Autodesk Fusion 360 part; units mm, degrees
(part 3 of 3)
sketch "V3 label POWER  /  LOCK  /  PURGE" plane through (0, 0, 67) normal (0, 0, 1) x (1, 0, 0) in component "02 LID - LCD buttons LEDs"
  line L0 (10, 78) -> (130, 78) construction
  line L1 (130, 78) -> (130, 86) construction
  line L2 (130, 86) -> (10, 86) construction
  line L3 (10, 86) -> (10, 78) construction
  dimension "d880" = 4
  text T0 "POWER  /  LOCK  /  PURGE" font "Arial" height 4 align centre middle in box 120 x 8 at (10, 78) x (1, 0) y (0, 1) spacing 1 kerned
extrude "V3 engraving POWER  /  LOCK  /  PURGE" cut sketch "V3 label POWER  /  LOCK  /  PURGE" against normal blind 0.6 text T0 bodies 2 in component "02 LID - LCD buttons LEDs"
ref_plane "WorkPlane44" through (0, 0, 67) normal (0, 0, 1) x (1, 0, 0) in component "02 LID - LCD buttons LEDs"
sketch "V3 label CONTROL UNIT" plane through (0, 0, 67) normal (0, 0, 1) x (1, 0, 0) in component "02 LID - LCD buttons LEDs"
  line L0 (20, 11) -> (120, 11) construction
  line L1 (120, 11) -> (120, 19) construction
  line L2 (120, 19) -> (20, 19) construction
  line L3 (20, 19) -> (20, 11) construction
  dimension "d886" = 4
  text T0 "CONTROL UNIT" font "Arial" height 4 align centre middle in box 100 x 8 at (20, 11) x (1, 0) y (0, 1) spacing 1 kerned
extrude "V3 engraving CONTROL UNIT" cut sketch "V3 label CONTROL UNIT" against normal blind 0.6 text T0 bodies 2 in component "02 LID - LCD buttons LEDs"
ref_plane "WorkPlane12" through (0, 0, 68.9) normal (0, 0, 1) x (1, 0, 0) in component "V2 removable control fascia"
sketch "V3 tactile number bars sketch" plane through (0, 0, 68.9) normal (0, 0, 1) x (1, 0, 0) in component "V2 removable control fascia"
  line L0 (61.98, 60) -> (62.78, 60)
  line L1 (62.78, 60) -> (62.78, 63.2)
  line L2 (62.78, 63.2) -> (61.98, 63.2)
  line L3 (61.98, 63.2) -> (61.98, 60)
extrude "V3 tactile number bars" cut sketch "V3 tactile number bars sketch" along normal blind 0.8 bodies 7 in component "V2 removable control fascia"
ref_plane "WorkPlane13" through (0, 0, 68.9) normal (0, 0, 1) x (1, 0, 0) in component "V2 removable control fascia"
sketch "V3 tactile number bars sketch (1)" plane through (0, 0, 68.9) normal (0, 0, 1) x (1, 0, 0) in component "V2 removable control fascia"
  line L0 (68.8, 60) -> (69.6, 60)
  line L1 (69.6, 60) -> (69.6, 63.2)
  line L2 (69.6, 63.2) -> (68.8, 63.2)
  line L3 (68.8, 63.2) -> (68.8, 60)
extrude "V3 tactile number bars (1)" cut sketch "V3 tactile number bars sketch (1)" along normal blind 0.8 bodies 7 in component "V2 removable control fascia"
ref_plane "WorkPlane14" through (0, 0, 68.9) normal (0, 0, 1) x (1, 0, 0) in component "V2 removable control fascia"
sketch "V3 tactile number bars sketch (2)" plane through (0, 0, 68.9) normal (0, 0, 1) x (1, 0, 0) in component "V2 removable control fascia"
  line L0 (70.4, 60) -> (71.2, 60)
  line L1 (71.2, 60) -> (71.2, 63.2)
  line L2 (71.2, 63.2) -> (70.4, 63.2)
  line L3 (70.4, 63.2) -> (70.4, 60)
extrude "V3 tactile number bars (2)" cut sketch "V3 tactile number bars sketch (2)" along normal blind 0.8 bodies 7 in component "V2 removable control fascia"
ref_plane "WorkPlane15" through (0, 0, 68.9) normal (0, 0, 1) x (1, 0, 0) in component "V2 removable control fascia"
sketch "V3 tactile number bars sketch (3)" plane through (0, 0, 68.9) normal (0, 0, 1) x (1, 0, 0) in component "V2 removable control fascia"
  line L0 (75.62, 60) -> (76.42, 60)
  line L1 (76.42, 60) -> (76.42, 63.2)
  line L2 (76.42, 63.2) -> (75.62, 63.2)
  line L3 (75.62, 63.2) -> (75.62, 60)
extrude "V3 tactile number bars (3)" cut sketch "V3 tactile number bars sketch (3)" along normal blind 0.8 bodies 7 in component "V2 removable control fascia"
ref_plane "WorkPlane16" through (0, 0, 68.9) normal (0, 0, 1) x (1, 0, 0) in component "V2 removable control fascia"
sketch "V3 tactile number bars sketch (4)" plane through (0, 0, 68.9) normal (0, 0, 1) x (1, 0, 0) in component "V2 removable control fascia"
  line L0 (77.22, 60) -> (78.02, 60)
  line L1 (78.02, 60) -> (78.02, 63.2)
  line L2 (78.02, 63.2) -> (77.22, 63.2)
  line L3 (77.22, 63.2) -> (77.22, 60)
extrude "V3 tactile number bars (4)" cut sketch "V3 tactile number bars sketch (4)" along normal blind 0.8 bodies 7 in component "V2 removable control fascia"
ref_plane "WorkPlane17" through (0, 0, 68.9) normal (0, 0, 1) x (1, 0, 0) in component "V2 removable control fascia"
sketch "V3 tactile number bars sketch (5)" plane through (0, 0, 68.9) normal (0, 0, 1) x (1, 0, 0) in component "V2 removable control fascia"
  line L0 (78.82, 60) -> (79.62, 60)
  line L1 (79.62, 60) -> (79.62, 63.2)
  line L2 (79.62, 63.2) -> (78.82, 63.2)
  line L3 (78.82, 63.2) -> (78.82, 60)
extrude "V3 tactile number bars (5)" cut sketch "V3 tactile number bars sketch (5)" along normal blind 0.8 bodies 7 in component "V2 removable control fascia"
ref_plane "WorkPlane1" through (0, 0, 8) normal (0, 0, 1) x (1, 0, 0) in component "REF relay envelope 75.5x55x20 - variant not confirmed"
sketch "Relay PCB envelope sketch" plane through (0, 0, 8) normal (0, 0, 1) x (1, 0, 0) in component "REF relay envelope 75.5x55x20 - variant not confirmed"
  line L0 (32.25, 112) -> (107.75, 112)
  line L1 (107.75, 112) -> (107.75, 167)
  line L2 (107.75, 167) -> (32.25, 167)
  line L3 (32.25, 167) -> (32.25, 112)
extrude "Relay PCB envelope" add sketch "Relay PCB envelope sketch" along normal blind 1.6 separate body makes body 33 in component "REF relay envelope 75.5x55x20 - variant not confirmed"
ref_plane "WorkPlane2" through (0, 0, 9.6) normal (0, 0, 1) x (1, 0, 0) in component "REF relay envelope 75.5x55x20 - variant not confirmed"
sketch "SRD relay envelope 1 sketch" plane through (0, 0, 9.6) normal (0, 0, 1) x (1, 0, 0) in component "REF relay envelope 75.5x55x20 - variant not confirmed"
  line L0 (36.75, 131) -> (52.25, 131)
  line L1 (52.25, 131) -> (52.25, 150)
  line L2 (52.25, 150) -> (36.75, 150)
  line L3 (36.75, 150) -> (36.75, 131)
extrude "SRD relay envelope 1" add sketch "SRD relay envelope 1 sketch" along normal blind 15.5 separate body makes body 34 in component "REF relay envelope 75.5x55x20 - variant not confirmed"
ref_plane "WorkPlane3" through (0, 0, 9.6) normal (0, 0, 1) x (1, 0, 0) in component "REF relay envelope 75.5x55x20 - variant not confirmed"
sketch "SRD relay envelope 2 sketch" plane through (0, 0, 9.6) normal (0, 0, 1) x (1, 0, 0) in component "REF relay envelope 75.5x55x20 - variant not confirmed"
  line L0 (54.05, 131) -> (69.55, 131)
  line L1 (69.55, 131) -> (69.55, 150)
  line L2 (69.55, 150) -> (54.05, 150)
  line L3 (54.05, 150) -> (54.05, 131)
extrude "SRD relay envelope 2" add sketch "SRD relay envelope 2 sketch" along normal blind 15.5 separate body makes body 35 in component "REF relay envelope 75.5x55x20 - variant not confirmed"
ref_plane "WorkPlane4" through (0, 0, 9.6) normal (0, 0, 1) x (1, 0, 0) in component "REF relay envelope 75.5x55x20 - variant not confirmed"
sketch "SRD relay envelope 3 sketch" plane through (0, 0, 9.6) normal (0, 0, 1) x (1, 0, 0) in component "REF relay envelope 75.5x55x20 - variant not confirmed"
  line L0 (71.35, 131) -> (86.85, 131)
  line L1 (86.85, 131) -> (86.85, 150)
  line L2 (86.85, 150) -> (71.35, 150)
  line L3 (71.35, 150) -> (71.35, 131)
extrude "SRD relay envelope 3" add sketch "SRD relay envelope 3 sketch" along normal blind 15.5 separate body makes body 36 in component "REF relay envelope 75.5x55x20 - variant not confirmed"
ref_plane "WorkPlane5" through (0, 0, 9.6) normal (0, 0, 1) x (1, 0, 0) in component "REF relay envelope 75.5x55x20 - variant not confirmed"
sketch "SRD relay envelope 4 sketch" plane through (0, 0, 9.6) normal (0, 0, 1) x (1, 0, 0) in component "REF relay envelope 75.5x55x20 - variant not confirmed"
  line L0 (88.65, 131) -> (104.15, 131)
  line L1 (104.15, 131) -> (104.15, 150)
  line L2 (104.15, 150) -> (88.65, 150)
  line L3 (88.65, 150) -> (88.65, 131)
extrude "SRD relay envelope 4" add sketch "SRD relay envelope 4 sketch" along normal blind 15.5 separate body makes body 37 in component "REF relay envelope 75.5x55x20 - variant not confirmed"
ref_plane "WorkPlane6" through (0, 0, 9.6) normal (0, 0, 1) x (1, 0, 0) in component "REF relay envelope 75.5x55x20 - variant not confirmed"
sketch "Terminal strip envelope sketch" plane through (0, 0, 9.6) normal (0, 0, 1) x (1, 0, 0) in component "REF relay envelope 75.5x55x20 - variant not confirmed"
  line L0 (37, 155) -> (103, 155)
  line L1 (103, 155) -> (103, 165)
  line L2 (103, 165) -> (37, 165)
  line L3 (37, 165) -> (37, 155)
extrude "Terminal strip envelope" add sketch "Terminal strip envelope sketch" along normal blind 12 separate body makes body 38 in component "REF relay envelope 75.5x55x20 - variant not confirmed"
ref_plane "WorkPlane7" through (0, 0, 9.6) normal (0, 0, 1) x (1, 0, 0) in component "REF relay envelope 75.5x55x20 - variant not confirmed"
sketch "Control connector reserve sketch" plane through (0, 0, 9.6) normal (0, 0, 1) x (1, 0, 0) in component "REF relay envelope 75.5x55x20 - variant not confirmed"
  line L0 (41, 114) -> (77, 114)
  line L1 (77, 114) -> (77, 119)
  line L2 (77, 119) -> (41, 119)
  line L3 (41, 119) -> (41, 114)
extrude "Control connector reserve" add sketch "Control connector reserve sketch" along normal blind 18.4 separate body makes body 39 in component "REF relay envelope 75.5x55x20 - variant not confirmed"
ref_plane "WorkPlane1" through (0, 0, 49.6) normal (0, 0, 1) x (1, 0, 0) in component "REF LCD2004 98x60 - 93x55 mounting - conservative thickness"
sketch "LCD PCB 98x60 sketch" plane through (0, 0, 49.6) normal (0, 0, 1) x (1, 0, 0) in component "REF LCD2004 98x60 - 93x55 mounting - conservative thickness"
  line L0 (21, 98) -> (119, 98)
  line L1 (119, 98) -> (119, 158)
  line L2 (119, 158) -> (21, 158)
  line L3 (21, 158) -> (21, 98)
extrude "LCD PCB 98x60" add sketch "LCD PCB 98x60 sketch" along normal blind 1.6 separate body makes body 40 in component "REF LCD2004 98x60 - 93x55 mounting - conservative thickness"
ref_plane "WorkPlane2" through (0, 0, 49.5) normal (0, 0, 1) x (1, 0, 0) in component "REF LCD2004 98x60 - 93x55 mounting - conservative thickness"
sketch "LCD minimum published hole diameter sketch" plane through (0, 0, 49.5) normal (0, 0, 1) x (1, 0, 0) in component "REF LCD2004 98x60 - 93x55 mounting - conservative thickness"
  circle A0 centre (23.5, 100.5) radius 1.25
  circle A1 centre (116.5, 100.5) radius 1.25
  circle A2 centre (23.5, 155.5) radius 1.25
  circle A3 centre (116.5, 155.5) radius 1.25
extrude "LCD minimum published hole diameter" cut sketch "LCD minimum published hole diameter sketch" along normal blind 1.8 bodies 40 in component "REF LCD2004 98x60 - 93x55 mounting - conservative thickness"
ref_plane "WorkPlane3" through (0, 0, 51.2) normal (0, 0, 1) x (1, 0, 0) in component "REF LCD2004 98x60 - 93x55 mounting - conservative thickness"
sketch "LCD bezel depth envelope sketch" plane through (0, 0, 51.2) normal (0, 0, 1) x (1, 0, 0) in component "REF LCD2004 98x60 - 93x55 mounting - conservative thickness"
  line L0 (21.5, 108.8) -> (118.5, 108.8)
  line L1 (118.5, 108.8) -> (118.5, 147.2)
  line L2 (118.5, 147.2) -> (21.5, 147.2)
  line L3 (21.5, 147.2) -> (21.5, 108.8)
extrude "LCD bezel depth envelope" add sketch "LCD bezel depth envelope sketch" along normal blind 12 separate body makes body 41 in component "REF LCD2004 98x60 - 93x55 mounting - conservative thickness"
ref_plane "WorkPlane4" through (0, 0, 63.2) normal (0, 0, 1) x (1, 0, 0) in component "REF LCD2004 98x60 - 93x55 mounting - conservative thickness"
sketch "LCD viewing area envelope sketch" plane through (0, 0, 63.2) normal (0, 0, 1) x (1, 0, 0) in component "REF LCD2004 98x60 - 93x55 mounting - conservative thickness"
  line L0 (31.5, 115.4) -> (108.5, 115.4)
  line L1 (108.5, 115.4) -> (108.5, 140.6)
  line L2 (108.5, 140.6) -> (31.5, 140.6)
  line L3 (31.5, 140.6) -> (31.5, 115.4)
extrude "LCD viewing area envelope" add sketch "LCD viewing area envelope sketch" along normal blind 0.1 separate body makes body 42 in component "REF LCD2004 98x60 - 93x55 mounting - conservative thickness"
ref_plane "WorkPlane5" through (0, 0, 39.2) normal (0, 0, 1) x (1, 0, 0) in component "REF LCD2004 98x60 - 93x55 mounting - conservative thickness"
sketch "LCD I2C backpack reserve sketch" plane through (0, 0, 39.2) normal (0, 0, 1) x (1, 0, 0) in component "REF LCD2004 98x60 - 93x55 mounting - conservative thickness"
  line L0 (32, 100) -> (74, 100)
  line L1 (74, 100) -> (74, 118)
  line L2 (74, 118) -> (32, 118)
  line L3 (32, 118) -> (32, 100)
extrude "LCD I2C backpack reserve" add sketch "LCD I2C backpack reserve sketch" along normal blind 10.4 separate body makes body 43 in component "REF LCD2004 98x60 - 93x55 mounting - conservative thickness"
component "01 BASE - PCB at bottom" placed x (1, 0, 0) y (0, 1, 0) z (0, 0, 1) at (0, 0, 0)
component "02 LID - LCD buttons LEDs" placed x (1, 0, 0) y (0, 1, 0) z (0, 0, 1) at (0, 0, 0)
component "V2 MAIN clamp 1" placed x (1, 0, 0) y (0, 1, 0) z (0, 0, 1) at (0, 0, 0)
component "V2 MAIN clamp 2" placed x (1, 0, 0) y (0, 1, 0) z (0, 0, 1) at (0, 0, 0)
component "V2 MAIN clamp 3" placed x (1, 0, 0) y (0, 1, 0) z (0, 0, 1) at (0, 0, 0)
component "V2 MAIN clamp 4" placed x (1, 0, 0) y (0, 1, 0) z (0, 0, 1) at (0, 0, 0)
component "V2 removable control fascia" placed x (1, 0, 0) y (0, 1, 0) z (0, 0, 1) at (0, 0, 0)
component "V2 control PCB removable carrier" placed x (1, 0, 0) y (0, 1, 0) z (0, 0, 1) at (0, 0, 0)
component "V2 captured tactile plunger 1" placed x (1, 0, 0) y (0, 1, 0) z (0, 0, 1) at (0, 0, 0)
component "V2 captured tactile plunger 2" placed x (1, 0, 0) y (0, 1, 0) z (0, 0, 1) at (0, 0, 0)
component "V2 captured tactile plunger 3" placed x (1, 0, 0) y (0, 1, 0) z (0, 0, 1) at (0, 0, 0)
component "REF main board 90x80x20 - photo estimate" placed x (1, 0, 0) y (0, 1, 0) z (0, 0, 1) at (0, 0, 0)
component "REF actual combined buttons LEDs PCB - estimated" placed x (1, 0, 0) y (0, 1, 0) z (0, 0, 1) at (0, 0, 0)
component "V3 RELAY adjustable clamp 1" placed x (1, 0, 0) y (0, 1, 0) z (0, 0, 1) at (0, 0, 0)
component "V3 RELAY adjustable clamp 2" placed x (1, 0, 0) y (0, 1, 0) z (0, 0, 1) at (0, 0, 0)
component "V3 RELAY adjustable clamp 3" placed x (1, 0, 0) y (0, 1, 0) z (0, 0, 1) at (0, 0, 0)
component "V3 RELAY adjustable clamp 4" placed x (1, 0, 0) y (0, 1, 0) z (0, 0, 1) at (0, 0, 0)
component "REF relay envelope 75.5x55x20 - variant not confirmed" placed x (1, 0, 0) y (0, 1, 0) z (0, 0, 1) at (0, 0, 0)
component "REF LCD2004 98x60 - 93x55 mounting - conservative thickness" placed x (1, 0, 0) y (0, 1, 0) z (0, 0, 1) at (0, 0, 0)
equation "button_d = 12.2 mm" comment "ASSUMED: measure actual panel button"
equation "led_d = 5.2 mm" comment "ASSUMED: 5 mm LED clearance"
equation "screw_clearance = 3.4 mm" comment "M3 clearance"
equation "pilot_d = 2.5 mm" comment "Plastic tapping pilot; verify printed fit"
equation "d17 = pilot_d"
equation "d18 = pilot_d"
equation "d19 = pilot_d"
equation "d20 = pilot_d"
equation "d37 = pilot_d"
equation "d38 = pilot_d"
equation "d39 = pilot_d"
equation "d40 = pilot_d"
equation "d53 = screw_clearance"
equation "d54 = screw_clearance"
equation "d55 = screw_clearance"
equation "d56 = screw_clearance"
equation "d73 = pilot_d"
equation "d74 = pilot_d"
equation "d75 = pilot_d"
equation "d76 = pilot_d"
equation "d81 = button_d"
equation "d82 = button_d"
equation "d83 = button_d"
equation "d88 = led_d"
equation "d89 = led_d"
equation "d90 = led_d"
equation "d96 = 'H2 PRO'"
equation "d102 = 'POWER'"
equation "d108 = 'LOCK'"
equation "d114 = 'PURGE'"
equation "d120 = 'POWER'"
equation "d126 = 'LOCK'"
equation "d132 = 'MODE'"
equation "d408 = 'H2 PRO'"
equation "d414 = 'BRAIN / CONTROL UNIT'"
equation "d420 = 'POWER   LOCK   PURGE'"
equation "d426 = 'STATUS INDICATORS'"
equation "d448 = '1'"
equation "d454 = '2'"
equation "d460 = '3'"
equation "v3_lip_gap = 0.5 mm" comment "PETG removable cover lateral gap each side"
equation "v3_m3_clear = 3.6 mm" comment "M3 clearance for nozzle 0.6"
equation "v3_button_guide = 6.3 mm" comment "Guide for 5.5 mm plunger: 0.4 mm radial clearance"
equation "v3_switch_height = 4.3 mm" comment "Reference B3F-1000 height; actual unmarked switch requires fit check"
equation "v3_relay_w = 75.5 mm" comment "Envelope of documented Addicore variants; not positively identified"
equation "v3_relay_l = 55 mm" comment "Largest documented plan length"
equation "v3_lcd_standoff = 12.8 mm" comment "PCB front to lid underside; conservative 12 mm bezel plus 0.8 gap"
equation "v3_shrink_xy = 0.0030000000000000001" comment "TRIAL ONLY 0.3 percent; applied only by STL export utility, never to CAD"
equation "d713 = v3_m3_clear"
equation "d714 = v3_m3_clear"
equation "d715 = v3_m3_clear"
equation "d716 = v3_m3_clear"
equation "d829 = v3_button_guide"
equation "d830 = v3_button_guide"
equation "d831 = v3_button_guide"
equation "d836 = v3_m3_clear"
equation "d837 = v3_m3_clear"
equation "d838 = v3_m3_clear"
equation "d839 = v3_m3_clear"
equation "d844 = v3_m3_clear"
equation "d845 = v3_m3_clear"
equation "d875 = 'H2 PRO'"
equation "d881 = 'POWER  /  LOCK  /  PURGE'"
equation "d887 = 'CONTROL UNIT'"
named bodies: "BASE_V2_PRINT", "LID_V2_PRINT", "Tactile contact stem", "Main PCB", "ESP32 reference", "nRF24 reference", "MPU6050 reference", "Tallest component 20mm total", "Rocker switch side clearance", "SMA connector space", "Control PCB estimated 30x30", "Tactile switch 6x6", "Switch actuator", "Tactile switch 6x6 (1)", "Switch actuator (1)", "Tactile switch 6x6 (2)", "Switch actuator (2)", "LED BLUE", "LED RED", "LED GREEN", "Relay PCB envelope", "SRD relay envelope 1", "SRD relay envelope 2", "SRD relay envelope 3", "SRD relay envelope 4", "Terminal strip envelope", "Control connector reserve", "LCD PCB 98x60", "LCD bezel depth envelope", "LCD viewing area envelope", "LCD I2C backpack reserve"
